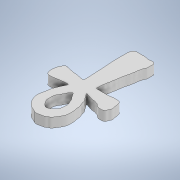
# Autodesk Inventor part: cruce
Saved by Autodesk Inventor 2022.6 (Build 266554000, 554)
## iProperties
Created: 2024-11-29
Part Number: cruce
Material: Generic
Document SubType Name: Modeling
Designer: Dragos Macovei
Density: 1 g/cm^3
Appearance: Default
Author: Dragos Macovei
Autodesk Inventor part; units mm, degrees
ref_plane "YZ Plane" through (0, 0, 0) normal (1, 0, 0) x (0, 1, 0)
ref_plane "XZ Plane" through (0, 0, 0) normal (0, 1, 0) x (-1, 0, 0)
ref_plane "XY Plane" through (0, 0, 0) normal (0, 0, 1) x (1, 0, 0)
sketch "Sketch1" plane through (0, 0, 0) normal (0, 1, 0) x (-1, 0, 0)
  line L0 (0, 0) -> (40, 0)
  line L1 (40, 0) -> (40, 40)
  line L2 (40, 40) -> (0, 40)
  line L3 (0, 40) -> (0, 0)
  line L4 (-181.9357, 357.184) -> (224.4643, 357.184) construction
  line L5 (224.4643, 357.184) -> (224.4643, -184.6827) construction
  line L6 (224.4643, -184.6827) -> (-181.9357, -184.6827) construction
  line L7 (-181.9357, -184.6827) -> (-181.9357, 357.184) construction
  line L8 (21.6301, 35.8455) -> (22.488, 35.3689) construction
  line L9 (22.488, 35.3689) -> (23.2188, 35.1783) construction
  line L10 (23.2188, 35.1783) -> (24.0449, 34.5428) construction
  line L11 (24.0449, 34.5428) -> (24.8074, 33.5897) construction
  line L12 (24.8074, 33.5897) -> (25.3158, 32.7) construction
  line L13 (25.3158, 32.7) -> (25.7606, 31.4609) construction
  line L14 (25.7606, 31.4609) -> (25.7606, 30.5712) construction
  line L15 (25.7606, 30.5712) -> (25.57, 29.5545) construction
  line L16 (25.57, 29.5545) -> (25.2522, 28.4425) construction
  line L17 (25.2522, 28.4425) -> (25.2522, 27.1715) construction
  line L18 (25.2522, 27.1715) -> (24.871, 26.409) construction
  line L19 (24.871, 26.409) -> (24.299, 24.7886) construction
  line L20 (24.299, 24.7886) -> (23.5683, 23.5177) construction
  line L21 (23.5683, 23.5177) -> (23.4962, 23.1099) construction
  line L22 (23.4962, 23.1099) -> (23.894, 23.1099) construction
  line L23 (23.894, 23.1099) -> (24.8338, 23.1099) construction
  line L24 (24.8338, 23.1099) -> (26.0036, 23.2516) construction
  line L25 (26.0036, 23.2516) -> (26.8994, 23.4097) construction
  line L26 (26.8994, 23.4097) -> (27.6688, 23.5783) construction
  line L27 (27.6688, 23.5783) -> (28.3854, 23.6626) construction
  line L28 (28.3854, 23.6626) -> (29.5131, 23.6626) construction
  line L29 (29.5131, 23.6626) -> (29.9452, 23.3886) construction
  line L30 (29.9452, 23.3886) -> (30.2614, 22.7984) construction
  line L31 (30.2614, 22.7984) -> (30.3457, 22.1345) construction
  line L32 (30.3457, 22.1345) -> (30.3457, 21.3968) construction
  line L33 (30.3457, 21.3968) -> (30.2403, 20.5747) construction
  line L34 (30.2403, 20.5747) -> (29.9768, 19.6789) construction
  line L35 (29.9768, 19.6789) -> (29.5342, 18.9201) construction
  line L36 (29.5342, 18.9201) -> (29.1337, 18.4458) construction
  line L37 (29.1337, 18.4458) -> (28.7121, 18.4458) construction
  line L38 (28.7121, 18.4458) -> (28.3854, 18.6039) construction
  line L39 (28.3854, 18.6039) -> (26.9943, 18.8885) construction
  line L40 (26.9943, 18.8885) -> (25.7416, 19.1241) construction
  line L41 (25.7416, 19.1241) -> (24.8044, 19.1241) construction
  line L42 (24.8044, 19.1241) -> (23.7463, 19.4567) construction
  line L43 (23.7463, 19.4567) -> (22.8999, 19.4567) construction
  line L44 (22.8999, 19.4567) -> (22.4162, 19.6985) construction
  line L45 (22.4162, 19.6985) -> (22.4162, 19.3444) construction
  line L46 (22.4162, 19.3444) -> (22.4162, 17.4785) construction
  line L47 (22.4162, 17.4785) -> (22.5657, 16.0113) construction
  line L48 (22.5657, 16.0113) -> (22.5657, 14.4325) construction
  line L49 (22.5657, 14.4325) -> (22.7411, 12.3753) construction
  line L50 (22.7411, 12.3753) -> (22.9324, 9.7121) construction
  line L51 (22.9324, 9.7121) -> (22.9324, 8.213) construction
  line L52 (22.9324, 8.213) -> (22.9324, 6.2674) construction
  line L53 (22.9324, 6.2674) -> (22.9324, 4.6248) construction
  line L54 (22.9324, 4.6248) -> (22.7092, 4.0986) construction
  line L55 (22.7092, 4.0986) -> (22.2945, 3.5883) construction
  line L56 (22.2945, 3.5883) -> (21.7842, 3.4926) construction
  line L57 (21.7842, 3.4926) -> (21.2643, 3.4926) construction
  line L58 (21.2643, 3.4926) -> (20.2533, 3.4926) construction
  line L59 (20.2533, 3.4926) -> (19.2645, 3.4926) construction
  line L60 (19.2645, 3.4926) -> (18.7156, 3.4926) construction
  line L61 (18.7156, 3.4926) -> (18.1209, 3.7664) construction
  line L62 (18.1209, 3.7664) -> (17.6141, 3.7664) construction
  line L63 (17.6141, 3.7664) -> (16.6489, 3.5734) construction
  line L64 (16.6489, 3.5734) -> (16.311, 3.5734) construction
  line L65 (16.311, 3.5734) -> (15.6836, 3.9112) construction
  line L66 (15.6836, 3.9112) -> (15.6836, 4.6352) construction
  line L67 (15.6836, 4.6352) -> (15.6836, 5.0695) construction
  line L68 (15.6836, 5.0695) -> (15.6836, 5.6004) construction
  line L69 (15.6836, 5.6004) -> (15.6836, 6.1313) construction
  line L70 (15.6836, 6.1313) -> (15.6836, 6.445) construction
  line L71 (15.6836, 6.445) -> (16.1421, 6.9518) construction
  line L72 (16.1421, 6.9518) -> (16.1421, 7.4103) construction
  line L73 (16.1421, 7.4103) -> (16.2869, 7.9412) construction
  line L74 (16.2869, 7.9412) -> (16.4317, 8.3273) construction
  line L75 (16.4317, 8.3273) -> (16.4317, 8.7858) construction
  line L76 (16.4317, 8.7858) -> (16.4317, 9.2925) construction
  line L77 (16.4317, 9.2925) -> (16.6489, 9.751) construction
  line L78 (16.6489, 9.751) -> (16.6489, 10.113) construction
  line L79 (16.6489, 10.113) -> (16.6489, 10.4267) construction
  line L80 (16.6489, 10.4267) -> (16.8178, 10.7404) construction
  line L81 (16.8178, 10.7404) -> (16.8178, 11.1024) construction
  line L82 (16.8178, 11.1024) -> (16.9867, 11.4161) construction
  line L83 (16.9867, 11.4161) -> (16.9867, 11.8022) construction
  line L84 (16.9867, 11.8022) -> (17.228, 12.3331) construction
  line L85 (17.228, 12.3331) -> (17.228, 12.864) construction
  line L86 (17.228, 12.864) -> (17.228, 13.2742) construction
  line L87 (17.228, 13.2742) -> (17.4211, 13.7327) construction
  line L88 (17.4211, 13.7327) -> (17.4211, 14.0947) construction
  line L89 (17.4211, 14.0947) -> (17.4211, 14.3843) construction
  line L90 (17.4211, 14.3843) -> (17.6383, 15.0358) construction
  line L91 (17.6383, 15.0358) -> (17.6383, 15.615) construction
  line L92 (17.6383, 15.615) -> (17.783, 16.363) construction
  line L93 (17.783, 16.363) -> (17.9278, 16.725) construction
  line L94 (17.9278, 16.725) -> (17.9278, 17.1835) construction
  line L95 (17.9278, 17.1835) -> (18.1209, 17.8592) construction
  line L96 (18.1209, 17.8592) -> (18.1209, 18.1729) construction
  line L97 (18.1209, 18.1729) -> (18.1209, 18.5349) construction
  line L98 (18.1209, 18.5349) -> (18.1209, 18.8244) construction
  line L99 (18.1209, 18.8244) -> (18.1209, 19.0658) construction
  line L100 (18.1209, 19.0658) -> (18.1209, 19.3312) construction
  line L101 (18.1209, 19.3312) -> (18.1209, 19.6208) construction
  line L102 (18.1209, 19.6208) -> (18.217, 19.8315) construction
  line L103 (18.217, 19.8315) -> (17.8601, 19.9045) construction
  line L104 (17.8601, 19.9045) -> (17.5114, 19.9045) construction
  line L105 (17.5114, 19.9045) -> (16.6825, 19.9045) construction
  line L106 (16.6825, 19.9045) -> (15.676, 19.9045) construction
  line L107 (15.676, 19.9045) -> (14.7638, 19.9045) construction
  line L108 (14.7638, 19.9045) -> (13.8202, 19.9045) construction
  line L109 (13.8202, 19.9045) -> (13.1911, 19.683) construction
  line L110 (13.1911, 19.683) -> (12.3733, 19.683) construction
  line L111 (12.3733, 19.683) -> (11.5869, 19.683) construction
  line L112 (11.5869, 19.683) -> (11.1466, 19.683) construction
  line L113 (11.1466, 19.683) -> (10.6433, 20) construction
  line L114 (10.6433, 20) -> (10.4231, 20.375) construction
  line L115 (10.4231, 20.375) -> (10.4231, 20.8153) construction
  line L116 (10.4231, 20.8153) -> (10.2029, 21.4759) construction
  line L117 (10.2029, 21.4759) -> (10.2029, 21.7904) construction
  line L118 (10.2029, 21.7904) -> (10.2029, 22.1364) construction
  line L119 (10.2029, 22.1364) -> (9.9828, 22.5139) construction
  line L120 (9.9828, 22.5139) -> (9.9828, 23.1115) construction
  line L121 (9.9828, 23.1115) -> (10.2658, 23.426) construction
  line L122 (10.2658, 23.426) -> (10.486, 23.9293) construction
  line L123 (10.486, 23.9293) -> (10.486, 24.4011) construction
  line L124 (10.486, 24.4011) -> (10.9264, 24.6213) construction
  line L125 (10.9264, 24.6213) -> (11.3038, 24.81) construction
  line L126 (11.3038, 24.81) -> (11.8071, 24.81) construction
  line L127 (11.8071, 24.81) -> (12.1217, 24.81) construction
  line L128 (12.1217, 24.81) -> (12.5935, 24.81) construction
  line L129 (12.5935, 24.81) -> (12.908, 24.5899) construction
  line L130 (12.908, 24.5899) -> (13.3484, 24.3382) construction
  line L131 (13.3484, 24.3382) -> (13.6315, 23.9922) construction
  line L132 (13.6315, 23.9922) -> (14.0404, 23.772) construction
  line L133 (14.0404, 23.772) -> (14.4178, 23.772) construction
  line L134 (14.4178, 23.772) -> (14.8582, 23.5204) construction
  line L135 (14.8582, 23.5204) -> (15.3929, 23.5204) construction
  line L136 (15.3929, 23.5204) -> (15.8333, 23.5204) construction
  line L137 (15.8333, 23.5204) -> (16.3994, 23.2688) construction
  line L138 (16.3994, 23.2688) -> (16.7769, 23.2688) construction
  line L139 (16.7769, 23.2688) -> (17.1543, 23.0486) construction
  line L140 (17.1543, 23.0486) -> (17.5947, 23.0486) construction
  line L141 (17.5947, 23.0486) -> (17.8778, 22.7655) construction
  line L142 (17.8778, 22.7655) -> (18.1923, 22.7655) construction
  line L143 (18.1923, 22.7655) -> (18.2365, 22.9153) construction
  line L144 (18.2365, 22.9153) -> (18.1303, 23.0353) construction
  line L145 (18.1303, 23.0353) -> (17.8221, 23.4786) construction
  line L146 (17.8221, 23.4786) -> (17.3993, 24.0476) construction
  line L147 (17.3993, 24.0476) -> (17.0051, 24.6238) construction
  line L148 (17.0051, 24.6238) -> (16.6108, 25.0787) construction
  line L149 (16.6108, 25.0787) -> (16.4592, 25.4123) construction
  line L150 (16.4592, 25.4123) -> (16.4592, 25.7762) construction
  line L151 (16.4592, 25.7762) -> (16.2469, 26.3221) construction
  line L152 (16.2469, 26.3221) -> (16.0043, 26.9286) construction
  line L153 (16.0043, 26.9286) -> (15.7617, 27.5048) construction
  line L154 (15.7617, 27.5048) -> (15.7617, 28.0204) construction
  line L155 (15.7617, 28.0204) -> (15.7617, 28.5359) construction
  line L156 (15.7617, 28.5359) -> (15.4888, 29.3547) construction
  line L157 (15.4888, 29.3547) -> (15.4888, 29.8703) construction
  line L158 (15.4888, 29.8703) -> (15.4888, 30.7194) construction
  line L159 (15.4888, 30.7194) -> (15.4888, 31.4169) construction
  line L160 (15.4888, 31.4169) -> (15.6404, 31.9628) construction
  line L161 (15.6404, 31.9628) -> (15.883, 32.539) construction
  line L162 (15.883, 32.539) -> (16.2166, 33.1456) construction
  line L163 (16.2166, 33.1456) -> (16.5502, 33.6914) construction
  line L164 (16.5502, 33.6914) -> (16.8231, 34.025) construction
  line L165 (16.8231, 34.025) -> (17.0354, 34.4193) construction
  line L166 (17.0354, 34.4193) -> (17.369, 34.9045) construction
  line L167 (17.369, 34.9045) -> (17.7026, 35.0561) construction
  line L168 (17.7026, 35.0561) -> (18.0362, 35.0561) construction
  line L169 (18.0362, 35.0561) -> (18.3698, 35.4504) construction
  line L170 (18.3698, 35.4504) -> (18.7944, 35.693) construction
  line L171 (18.7944, 35.693) -> (19.2493, 35.693) construction
  line L172 (19.2493, 35.693) -> (19.6435, 35.8455) construction
  line L173 (19.6435, 35.8455) -> (20, 35.8455) construction
  line L174 (20, 35.8455) -> (20.523, 36.0569) construction
  line L175 (20.523, 36.0569) -> (20.8869, 36.0569) construction
  line L176 (20.8869, 36.0569) -> (21.2643, 36.0569) construction
  line L177 (21.2643, 36.0569) -> (21.6301, 35.8455) construction
  spline S0 degree 4 poles (21.6301, 35.8455) (22.488, 35.3689) (23.2188, 35.1783) (24.0449, 34.5428) (24.8074, 33.5897) (25.3158, 32.7) (25.7606, 31.4609) (25.7606, 30.5712) (25.57, 29.5545) (25.2522, 28.4425) (25.2522, 27.1715) (24.871, 26.409) (24.299, 24.7886) (23.5683, 23.5177) (23.4962, 23.1099) (23.894, 23.1099) (24.8338, 23.1099) (26.0036, 23.2516) (26.8994, 23.4097) (27.6688, 23.5783) (28.3854, 23.6626) (29.5131, 23.6626) (29.9452, 23.3886) (30.2614, 22.7984) (30.3457, 22.1345) (30.3457, 21.3968) (30.2403, 20.5747) (29.9768, 19.6789) (29.5342, 18.9201) (29.1337, 18.4458) (28.7121, 18.4458) (28.3854, 18.6039) (26.9943, 18.8885) (25.7416, 19.1241) (24.8044, 19.1241) (23.7463, 19.4567) (22.8999, 19.4567) (22.4162, 19.6985) (22.4162, 19.3444) (22.4162, 17.4785) (22.5657, 16.0113) (22.5657, 14.4325) (22.7411, 12.3753) (22.9324, 9.7121) (22.9324, 8.213) (22.9324, 6.2674) (22.9324, 4.6248) (22.7092, 4.0986) (22.2945, 3.5883) (21.7842, 3.4926) (21.2643, 3.4926) (20.2533, 3.4926) (19.2645, 3.4926) (18.7156, 3.4926) (18.1209, 3.7664) (17.6141, 3.7664) (16.6489, 3.5734) (16.311, 3.5734) (15.6836, 3.9112) (15.6836, 4.6352) (15.6836, 5.0695) (15.6836, 5.6004) (15.6836, 6.1313) (15.6836, 6.445) (16.1421, 6.9518) (16.1421, 7.4103) (16.2869, 7.9412) (16.4317, 8.3273) (16.4317, 8.7858) (16.4317, 9.2925) (16.6489, 9.751) (16.6489, 10.113) (16.6489, 10.4267) (16.8178, 10.7404) (16.8178, 11.1024) (16.9867, 11.4161) (16.9867, 11.8022) (17.228, 12.3331) (17.228, 12.864) (17.228, 13.2742) (17.4211, 13.7327) (17.4211, 14.0947) (17.4211, 14.3843) (17.6383, 15.0358) (17.6383, 15.615) (17.783, 16.363) (17.9278, 16.725) (17.9278, 17.1835) (18.1209, 17.8592) (18.1209, 18.1729) (18.1209, 18.5349) (18.1209, 18.8244) (18.1209, 19.0658) (18.1209, 19.3312) (18.1209, 19.6208) (18.217, 19.8315) (17.8601, 19.9045) (17.5114, 19.9045) (16.6825, 19.9045) (15.676, 19.9045) (14.7638, 19.9045) (13.8202, 19.9045) (13.1911, 19.683) (12.3733, 19.683) (11.5869, 19.683) (11.1466, 19.683) (10.6433, 20) (10.4231, 20.375) (10.4231, 20.8153) (10.2029, 21.4759) (10.2029, 21.7904) (10.2029, 22.1364) (9.9828, 22.5139) (9.9828, 23.1115) (10.2658, 23.426) (10.486, 23.9293) (10.486, 24.4011) (10.9264, 24.6213) (11.3038, 24.81) (11.8071, 24.81) (12.1217, 24.81) (12.5935, 24.81) (12.908, 24.5899) (13.3484, 24.3382) (13.6315, 23.9922) (14.0404, 23.772) (14.4178, 23.772) (14.8582, 23.5204) (15.3929, 23.5204) (15.8333, 23.5204) (16.3994, 23.2688) (16.7769, 23.2688) (17.1543, 23.0486) (17.5947, 23.0486) (17.8778, 22.7655) (18.1923, 22.7655) (18.2365, 22.9153) (18.1303, 23.0353) (17.8221, 23.4786) (17.3993, 24.0476) (17.0051, 24.6238) (16.6108, 25.0787) (16.4592, 25.4123) (16.4592, 25.7762) (16.2469, 26.3221) (16.0043, 26.9286) (15.7617, 27.5048) (15.7617, 28.0204) (15.7617, 28.5359) (15.4888, 29.3547) (15.4888, 29.8703) (15.4888, 30.7194) (15.4888, 31.4169) (15.6404, 31.9628) (15.883, 32.539) (16.2166, 33.1456) (16.5502, 33.6914) (16.8231, 34.025) (17.0354, 34.4193) (17.369, 34.9045) (17.7026, 35.0561) (18.0362, 35.0561) (18.3698, 35.4504) (18.7944, 35.693) (19.2493, 35.693) (19.6435, 35.8455) (20, 35.8455) (20.523, 36.0569) (20.8869, 36.0569) (21.2643, 36.0569) (21.6301, 35.8455) knots 1 1 1 1 1 2 3 4 5 6 7 8 9 10 11 12 13 14 15 16 17 18 19 20 21 22 23 24 25 26 27 28 29 30 31 32 33 34 35 36 37 38 39 40 41 42 43 44 45 46 47 48 49 50 51 52 53 54 55 56 57 58 59 60 61 62 63 64 65 66 67 68 69 70 71 72 73 74 75 76 77 78 79 80 81 82 83 84 85 86 87 88 89 90 91 92 93 94 95 96 97 98 99 100 101 102 103 104 105 106 107 108 109 110 111 112 113 114 115 116 117 118 119 120 121 122 123 124 125 126 127 128 129 130 131 132 133 134 135 136 137 138 139 140 141 142 143 144 145 146 147 148 149 150 151 152 153 154 155 156 157 158 159 160 161 162 163 164 165 166 167 168 168 168 168 168
  line L178 (21.1002, 32.8861) -> (21.4841, 32.6781) construction
  line L179 (21.4841, 32.6781) -> (21.8041, 32.4542) construction
  line L180 (21.8041, 32.4542) -> (21.996, 32.1822) construction
  line L181 (21.996, 32.1822) -> (22.188, 31.9422) construction
  line L182 (22.188, 31.9422) -> (22.412, 31.6063) construction
  line L183 (22.412, 31.6063) -> (22.6519, 31.2543) construction
  line L184 (22.6519, 31.2543) -> (22.8119, 30.9664) construction
  line L185 (22.8119, 30.9664) -> (22.9079, 30.6144) construction
  line L186 (22.9079, 30.6144) -> (22.9079, 30.2145) construction
  line L187 (22.9079, 30.2145) -> (22.9079, 29.2546) construction
  line L188 (22.9079, 29.2546) -> (22.9079, 28.8227) construction
  line L189 (22.9079, 28.8227) -> (22.8119, 28.1828) construction
  line L190 (22.8119, 28.1828) -> (22.5399, 27.6868) construction
  line L191 (22.5399, 27.6868) -> (22.156, 27.0629) construction
  line L192 (22.156, 27.0629) -> (21.884, 26.647) construction
  line L193 (21.884, 26.647) -> (21.5481, 26.0071) construction
  line L194 (21.5481, 26.0071) -> (21.3881, 25.4792) construction
  line L195 (21.3881, 25.4792) -> (20.9402, 25.0472) construction
  line L196 (20.9402, 25.0472) -> (20.6202, 24.7113) construction
  line L197 (20.6202, 24.7113) -> (20.4442, 24.8072) construction
  line L198 (20.4442, 24.8072) -> (20.2843, 24.9832) construction
  line L199 (20.2843, 24.9832) -> (20.1243, 25.2552) construction
  line L200 (20.1243, 25.2552) -> (19.8843, 25.5751) construction
  line L201 (19.8843, 25.5751) -> (19.6604, 25.9431) construction
  line L202 (19.6604, 25.9431) -> (19.4684, 26.215) construction
  line L203 (19.4684, 26.215) -> (19.2444, 26.487) construction
  line L204 (19.2444, 26.487) -> (18.9725, 26.759) construction
  line L205 (18.9725, 26.759) -> (18.7805, 27.0789) construction
  line L206 (18.7805, 27.0789) -> (18.7805, 27.4469) construction
  line L207 (18.7805, 27.4469) -> (18.5565, 27.7508) construction
  line L208 (18.5565, 27.7508) -> (18.4285, 28.0228) construction
  line L209 (18.4285, 28.0228) -> (18.2846, 28.3907) construction
  line L210 (18.2846, 28.3907) -> (18.1566, 28.7427) construction
  line L211 (18.1566, 28.7427) -> (18.1566, 29.0946) construction
  line L212 (18.1566, 29.0946) -> (18.1566, 29.5586) construction
  line L213 (18.1566, 29.5586) -> (18.1566, 30.0225) construction
  line L214 (18.1566, 30.0225) -> (18.3006, 30.4224) construction
  line L215 (18.3006, 30.4224) -> (18.3006, 30.8384) construction
  line L216 (18.3006, 30.8384) -> (18.4765, 31.0943) construction
  line L217 (18.4765, 31.0943) -> (18.5725, 31.3823) construction
  line L218 (18.5725, 31.3823) -> (18.7645, 31.6863) construction
  line L219 (18.7645, 31.6863) -> (18.9725, 32.0062) construction
  line L220 (18.9725, 32.0062) -> (19.3084, 32.1662) construction
  line L221 (19.3084, 32.1662) -> (19.6124, 32.3902) construction
  line L222 (19.6124, 32.3902) -> (19.8203, 32.5501) construction
  line L223 (19.8203, 32.5501) -> (20.1563, 32.7581) construction
  line L224 (20.1563, 32.7581) -> (20.3963, 32.8861) construction
  line L225 (20.3963, 32.8861) -> (20.7642, 32.9821) construction
  line L226 (20.7642, 32.9821) -> (21.1002, 32.8861) construction
  spline S1 degree 4 poles (21.1002, 32.8861) (21.4841, 32.6781) (21.8041, 32.4542) (21.996, 32.1822) (22.188, 31.9422) (22.412, 31.6063) (22.6519, 31.2543) (22.8119, 30.9664) (22.9079, 30.6144) (22.9079, 30.2145) (22.9079, 29.2546) (22.9079, 28.8227) (22.8119, 28.1828) (22.5399, 27.6868) (22.156, 27.0629) (21.884, 26.647) (21.5481, 26.0071) (21.3881, 25.4792) (20.9402, 25.0472) (20.6202, 24.7113) (20.4442, 24.8072) (20.2843, 24.9832) (20.1243, 25.2552) (19.8843, 25.5751) (19.6604, 25.9431) (19.4684, 26.215) (19.2444, 26.487) (18.9725, 26.759) (18.7805, 27.0789) (18.7805, 27.4469) (18.5565, 27.7508) (18.4285, 28.0228) (18.2846, 28.3907) (18.1566, 28.7427) (18.1566, 29.0946) (18.1566, 29.5586) (18.1566, 30.0225) (18.3006, 30.4224) (18.3006, 30.8384) (18.4765, 31.0943) (18.5725, 31.3823) (18.7645, 31.6863) (18.9725, 32.0062) (19.3084, 32.1662) (19.6124, 32.3902) (19.8203, 32.5501) (20.1563, 32.7581) (20.3963, 32.8861) (20.7642, 32.9821) (21.1002, 32.8861) knots 1 1 1 1 1 2 3 4 5 6 7 8 9 10 11 12 13 14 15 16 17 18 19 20 21 22 23 24 25 26 27 28 29 30 31 32 33 34 35 36 37 38 39 40 41 42 43 44 45 46 47 47 47 47 47
  dimension "d0" = 40
  dimension "d1" = 40
  constraints: 52 vertical, 35 horizontal, 8 end point, 2 parallel, 1 perpendicular, 4 other
  measures "d0" distance of L2.end L1.end
  measures "d1" distance of L1.end L0.end
extrude "Extrusion1" add sketch "Sketch1" along normal blind 3 contours S0
body "Solid1"
